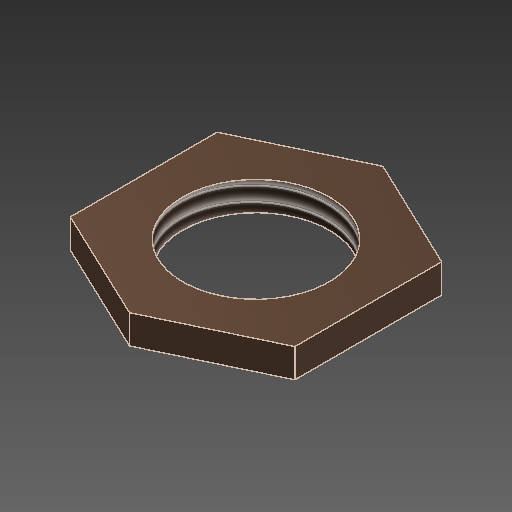
# Autodesk Inventor part: Tuerca
Saved by Autodesk Inventor 2026.1 (Build 301233020, 233B)
## iProperties
Created: 2026-10-26
Part Number: Tuerca
Material: Bronze, Cast
Document SubType Name: Modeling
Designer: YmCris
Density: 8.87 g/cm^3
Appearance: Bronze - Satin
Author: YmCris
Autodesk Inventor part; units mm, degrees
ref_plane "YZ Plane" through (0, 0, 0) normal (1, 0, 0) x (0, 1, 0)
ref_plane "XZ Plane" through (0, 0, 0) normal (0, 1, 0) x (-1, 0, 0)
ref_plane "XY Plane" through (0, 0, 0) normal (0, 0, 1) x (1, 0, 0)
sketch "Sketch1" plane through (0, 0, 0) normal (0, 1, 0) x (-1, 0, 0)
  circle A0 centre (0, 0) radius 25.5
  line L0 (-39, 0) -> (-39, -25.5)
  line L1 (39, 0) -> (39, -25.5)
  line L2 (-39, 0) -> (-39, 25.5)
  line L3 (39, 0) -> (39, 25.5)
  line L4 (39, -25.5) -> (-0.0737, -44.0349)
  line L5 (-0.0737, -44.0349) -> (-39, -25.5)
  line L6 (39, 25.5) -> (-0.0737, 44.0349)
  line L7 (-0.0737, 44.0349) -> (-39, 25.5)
  dimension "d14" = 25.5
  dimension "d16" = 51
  constraints: 16 end point, 1 centre point, 1 coincident, 1 vertical
  measures "d14" distance of L0.start L0.end
  measures "d16" distance of L3.end L1.end
extrude "Extrusion1" add sketch "Sketch1" along normal blind 10
thread "Thread1" size "M52x5" class "6H" standard "ANSI Metric M Profile" full length
body "Solid1"
